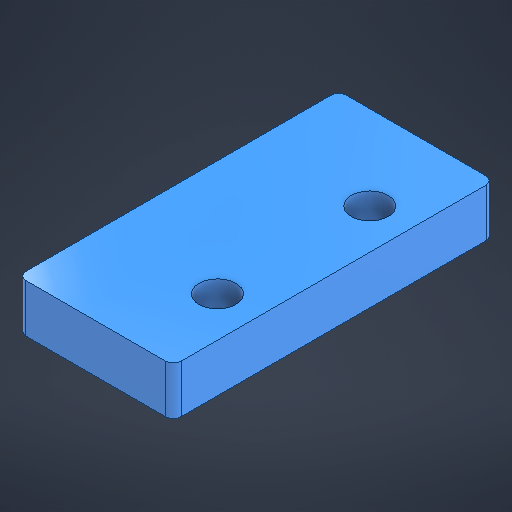
# Autodesk Inventor part: Limit Switch Spacer
Saved by Autodesk Inventor 2027.1 (Build 311270010, 270A)
## iProperties
Created: 2026-10-12
Part Number: Limit Switch Spacer
Material: Generic
Document SubType Name: Modeling
Designer: Ahmed
Density: 1 g/cm^3
Appearance: Cyan
Author: Ahmed
Autodesk Inventor part; units mm, degrees
ref_plane "YZ Plane" through (0, 0, 0) normal (1, 0, 0) x (0, 1, 0)
ref_plane "XZ Plane" through (0, 0, 0) normal (0, 1, 0) x (-1, 0, 0)
ref_plane "XY Plane" through (0, 0, 0) normal (0, 0, 1) x (1, 0, 0)
sketch "Sketch1" plane through (0, 0, 0) normal (0, 1, 0) x (-1, 0, 0)
  line L0 (2.5, 10) -> (-2, 10)
  line L1 (-2.5, 9.5) -> (-2.5, -9.5)
  line L2 (-2, -10) -> (2.5, -10)
  line L3 (2.5, -10) -> (2.5, 10)
  line L4 (2.5, 10) -> (-2.5, -10) construction
  line L5 (-2.5, 10) -> (2.5, -10) construction
  arc A0 (-2, 10) -> (-2.5, 9.5) centre (-2, 9.5) ccw
  arc A1 (-2.5, -9.5) -> (-2, -10) centre (-2, -9.5) ccw
  line L6 (0, -10) -> (0, 10)
  circle A2 centre (0, 4.75) radius 1.15
  circle A3 centre (0, -4.75) radius 1.15
  point P0 (0, 0)
  dimension "d0" = 5
  dimension "d1" = 20
  dimension "d5" = 2.3
  dimension "d6" = 2.3
  dimension "d7" = 4.75
  dimension "d8" = 4.75
  constraints: 14 end point, 7 point on line, 4 centre point, 4 point on circle, 4 tangent, 3 midpoint, 2 parallel, 1 horizontal, 1 perpendicular
  measures "d0" distance of L2.end L4.end
  measures "d1" distance of L4.end L5.start
  measures "d5" diameter of A2
  measures "d6" diameter of A3
  measures "d7" distance of point (0, 0) A2.centre
  measures "d8" distance of point (0, 0) A3.centre
extrude "Extrusion1" add sketch "Sketch1" along normal blind 3 contours L3 L2 L6 A3 A2 L0 | L6 A2 A3 L2 A1 L1 A0 L0
thicken "Thicken1" operation add thickness 4.69 both sides no extend neighbours no toward (-1, 0, 0) faces at (-2.5, 1, -3.3333)
fillet "Fillet1" radius 0.5 2 edges at (-7.19, 1.5, 10) (-7.19, 1.5, -10)
equation "\"d6\" = d5"
equation "\"d8\" = d7"
body "Solid1"
